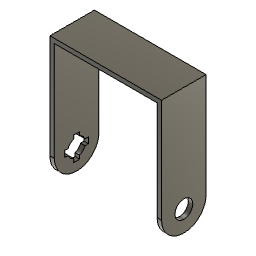
pierna (Autodesk Fusion 360 design; units mm, degrees)
Autodesk Fusion 360 part; units mm, degrees
sketch "Sketch1" plane through (0, 0, 0) normal (1, 0, 0) x (0, 1, 0)
  line L0 (0, 0) -> (30, 0)
  line L1 (30, 0) -> (30, 85)
  line L2 (30, 85) -> (0, 85)
  line L3 (0, 85) -> (0, 0)
  dimension "d1" = 30
  dimension "d32" = 85
  constraint horizontal L0
  constraint vertical L1
  constraint horizontal L2
  constraint vertical L3
  constraint coincident L0.start L3.end
  measures "d1" distance of L0.start L0.end
  measures "d32" distance of L0.start L2.end
extrude "Extrude1" add sketch "Sketch1" along normal blind 3
sketch "Sketch2" plane through (3, 0, 0) normal (1, 0, 0) x (0, 1, 0)
  line L0 (0, 85) -> (0, 0)
  line L1 (0, 0) -> (30, 0)
  line L2 (30, 0) -> (30, 85)
  line L3 (30, 85) -> (0, 85)
  point P0 (15, 11.8696)
  point P1 (15, 26.8696)
  dimension "d7" = 15
  measures "d7" distance of P0 P1
sketch "Sketch4" plane through (3, 0, 0) normal (1, 0, 0) x (0, 1, 0)
  line L0 (0, 85) -> (0, 0)
  line L1 (0, 0) -> (30, 0)
  line L2 (30, 0) -> (30, 85)
  line L3 (30, 85) -> (0, 85)
  circle A0 centre (15, 14) radius 6
  line L4 (17, 22) -> (13, 22)
  line L5 (13, 22) -> (13, 19.6569)
  line L6 (17, 19.6569) -> (17, 22)
  line L7 (17, 22) -> (13, 18) construction
  line L8 (13, 22) -> (17, 18) construction
  line L9 (7, 12) -> (9.3431, 12)
  line L10 (7, 16) -> (7, 12)
  line L11 (9.3431, 16) -> (7, 16)
  line L12 (17, 6) -> (17, 8.3431)
  line L13 (13, 6) -> (17, 6)
  line L14 (13, 8.3431) -> (13, 6)
  line L15 (23, 16) -> (20.6569, 16)
  line L16 (23, 12) -> (23, 16)
  line L17 (20.6569, 12) -> (23, 12)
  point P0 (15, 20)
  dimension "d16" = 12
  dimension "d17" = 14
  dimension "d18" = 15
  dimension "d19" = 4
  dimension "d20" = 4
  dimension "d22" = 360
  dimension "d23" = 2
  dimension "d24" = 8
  dimension "d25" = 2
  constraint horizontal L4
  constraint perpendicular L4 L5
  constraint parallel L5 L6
  constraint coincident L7 P0
  constraint coincident L8 P0
  constraint coincident A0 P0
  constraint coincident A0 L5.end
  constraint coincident A0 L6.start
  constraint perpendicular L7 L8
  measures "d16" diameter of A0
  measures "d17" vertical distance of L0.end A0.centre
  measures "d18" horizontal distance of L0.end A0.centre
  measures "d19" distance of L7.end L8.end
  measures "d20" distance of L4.end L7.end
  measures "d23" distance of L6 P0
  measures "d24" distance of A0.centre L4
  measures "d25" distance of L4 P0
extrude "Extrude3" cut sketch "Sketch4" against normal blind 3 contours A0 | A0 L15 L16 L17 | A0 L4 L5 L6 | A0 L12 L13 L14 | A0 L9 L10 L11
sketch "Sketch5" plane through (0, 0, 85) normal (0, 0, 1) x (-1, 0, 0)
  line L0 (0, -30) -> (0, 0)
  line L1 (0, 0) -> (-3, 0)
  line L2 (-3, 0) -> (-3, -30)
  line L3 (-3, -30) -> (0, -30)
  line L4 (0, -30) -> (-75.29, -30)
  line L5 (-75.29, -30) -> (-75.29, 0)
  line L6 (-75.29, 0) -> (0, 0)
  line L7 (0, 0) -> (0, -30)
  dimension "d28" = 75.29
  dimension "d29" = 30
  constraint horizontal L4
  constraint vertical L5
  constraint horizontal L6
  constraint vertical L7
  constraint coincident L0.start L3.end
  measures "d28" distance of L0.start L4.end
  measures "d29" distance of L0.start L0.end
extrude "Extrude4" add sketch "Sketch5" against normal blind 3 contours L2 L4 L5 L6
fillet "Fillet1" radius 15 2 edges at (1.5, 0, 0) (1.5, 30, 0)
sketch "Sketch6" plane through (0, 0, 82) normal (0, 0, -1) x (1, 0, 0)
  line L0 (75.29, -30) -> (75.29, 0)
  line L1 (75.29, 0) -> (3, 0)
  line L2 (3, 0) -> (3, -30)
  line L3 (3, -30) -> (75.29, -30)
  line L4 (75.29, 0) -> (72.29, 0)
  line L5 (72.29, 0) -> (72.29, -30)
  line L6 (72.29, -30) -> (75.29, -30)
  line L7 (75.29, -30) -> (75.29, 0)
  dimension "d37" = 3
  constraint horizontal L4
  constraint vertical L5
  constraint horizontal L6
  constraint vertical L7
  constraint coincident L0.end L1.start
  measures "d37" distance of L0.end L4.end
extrude "Extrude5" add sketch "Sketch6" along normal blind 82 contours L0 L1 L3 L4 L5 L6 L7
fillet "Fillet3" radius 15 2 edges at (73.79, 0, 0) (73.79, 30, 0)
sketch "Sketch7" plane through (75.29, 0, 0) normal (1, 0, 0) x (0, 1, 0)
  arc A0 (0, 15) -> (30, 15) centre (15, 15) ccw
  line L0 (30, 15) -> (30, 85)
  line L1 (30, 85) -> (0, 85)
  line L2 (0, 85) -> (0, 15)
  circle A1 centre (15, 14) radius 6
  dimension "d42" = 15
  dimension "d43" = 14
  dimension "d44" = 12
  measures "d42" horizontal distance of A1.centre origin
  measures "d43" vertical distance of A1.centre origin
  measures "d44" diameter of A1
extrude "Extrude6" cut sketch "Sketch7" against normal blind 10 contours A1
